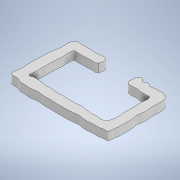
# Autodesk Inventor part: omega_patrat
Saved by Autodesk Inventor 2022.6 (Build 266554000, 554)
## iProperties
Created: 2024-11-29
Part Number: omega_patrat
Material: Generic
Document SubType Name: Modeling
Designer: Dragos Macovei
Density: 1 g/cm^3
Appearance: Default
Author: Dragos Macovei
Autodesk Inventor part; units mm, degrees
ref_plane "YZ Plane" through (0, 0, 0) normal (1, 0, 0) x (0, 1, 0)
ref_plane "XZ Plane" through (0, 0, 0) normal (0, 1, 0) x (-1, 0, 0)
ref_plane "XY Plane" through (0, 0, 0) normal (0, 0, 1) x (1, 0, 0)
sketch "Sketch1" plane through (0, 0, 0) normal (0, 1, 0) x (-1, 0, 0)
  line L0 (-66.777, 299.3906) -> (276.1714, 295.0556) construction
  line L1 (276.1714, 295.0556) -> (270.3914, -162.2089) construction
  line L2 (270.3914, -162.2089) -> (-72.557, -157.8739) construction
  line L3 (-72.557, -157.8739) -> (-66.777, 299.3906) construction
  line L4 (96.3483, 176.7256) -> (136.3483, 176.7256)
  line L5 (136.3483, 176.7256) -> (136.3483, 216.7256)
  line L6 (136.3483, 216.7256) -> (96.3483, 216.7256)
  line L7 (96.3483, 216.7256) -> (96.3483, 176.7256)
  spline S0 degree 5 poles (121.746, 189.6677) (121.8582, 189.8024) (122.1165, 190.0468) (122.696, 190.466) (123.267, 189.8642) (124.6453, 190.1774) (125.328, 190.0683) (126.8621, 190.3562) (128.3282, 190.0576) (129.112, 190.4967) (130.2239, 189.6634) (130.3851, 191.3616) (130.386, 192.2277) (130.4456, 193.2168) (130.098, 194.4317) (130.6414, 195.9554) (130.26, 197.268) (130.6866, 198.6376) (130.3499, 199.9474) (130.777, 201.8336) (130.3554, 202.4152) (130.6842, 203.8925) (130.4554, 204.6826) (130.7477, 205.6315) (130.835, 206.2315) (129.8137, 206.4041) (129.5759, 205.655) (128.3019, 205.9904) (127.631, 205.7744) (126.9754, 206.0105) (125.9738, 205.8252) (125.5897, 206.4444) (124.9227, 206.0743) (123.8224, 206.4023) (123.7203, 206.3457) (122.5113, 206.0601) (122.157, 206.5324) (121.0441, 206.2389) (120.3819, 206.6852) (119.6232, 206.4701) (117.036, 206.2938) (116.7323, 206.5852) (114.1771, 206.4506) (113.2716, 206.6097) (111.6878, 206.2504) (110.426, 206.1075) (109.1179, 206.8753) (108.3741, 206.3084) (107.0205, 207.3252) (105.4738, 206.2255) (104.5208, 207.1332) (101.2997, 206.9083) (101.9367, 204.5933) (101.1006, 204.794) (101.4951, 200.3084) (101.7262, 201.3801) (101.0749, 195.9532) (102.104, 194.9567) (100.8961, 191.7782) (102.0198, 190.7144) (102.3018, 191.2423) (103.3518, 191.0241) (104.1529, 191.0393) (104.914, 191.1531) (106.3556, 190.818) (106.9331, 190.6894) (107.5941, 190.7851) (108.6616, 191.0082) (109.5951, 190.8205) (110.226, 190.6347) (110.884, 189.6818) (110.3368, 188.8065) (110.3572, 188.1316) (110.5612, 187.3686) (109.7518, 186.984) (109.4345, 186.6326) (108.7664, 186.1921) (108.0478, 187.4743) (107.9195, 187.9274) (105.9688, 186.2366) (105.579, 187.9799) (104.6729, 187.6814) (103.1741, 187.3302) (102.2016, 187.7167) (100.7281, 186.8769) (100.1835, 188.1256) (99.0619, 187.4356) (98.5932, 188.7911) (98.2767, 189.0131) (98.2262, 190.1352) (98.1397, 191.5446) (98.2346, 192.1528) (98.3985, 194.3716) (98.073, 193.9662) (97.8455, 198.3926) (98.7798, 198.6808) (97.8366, 201.0867) (97.956, 202.903) (98.1221, 204.4291) (97.8543, 206.2027) (98.3732, 207.3771) (98.1322, 208.2019) (98.5683, 209.8021) (98.8147, 209.4139) (100.5555, 209.4661) (100.9972, 209.9948) (103.2743, 209.7444) (104.3228, 209.7586) (106.0751, 210.2206) (108.1074, 209.8047) (108.7444, 209.466) (110.6067, 209.9184) (111.2367, 209.9171) (113.9053, 210.0628) (114.3522, 209.9994) (116.608, 210.0205) (117.7825, 210.0415) (119.3895, 209.7172) (121.533, 210.2273) (123.3215, 209.4206) (124.9598, 209.8229) (126.838, 210.2204) (127.8277, 209.7644) (129.8941, 209.8151) (130.237, 209.8931) (131.5337, 208.8933) (131.8702, 209.3016) (132.5364, 208.9742) (133.6151, 209.2641) (134.5294, 208.8061) (134.7216, 207.7667) (133.6072, 204.6681) (134.7968, 202.1463) (133.8481, 198.4724) (134.5196, 195.9114) (133.1671, 191.4172) (133.6456, 189.992) (133.7121, 188.2772) (132.9584, 187.2211) (132.2502, 186.3053) (131.1337, 187.1404) (129.7612, 186.616) (128.3516, 187.0179) (126.5546, 186.7163) (125.4027, 187.4056) (124.0138, 186.438) (122.6452, 186.8345) (121.7613, 186.6506) (121.2217, 187.7352) (121.3717, 188.2192) (121.4927, 189.1283) (121.5396, 189.3738) (121.6519, 189.5549) (121.746, 189.6677) knots 0 0 0 0 0 0 0.006947 0.011757 0.018108 0.024839 0.031624 0.038107 0.044552 0.050761 0.056649 0.062728 0.069328 0.076188 0.083177 0.090521 0.09806 0.105274 0.1124 0.119309 0.125804 0.131543 0.136972 0.142021 0.147124 0.15223 0.157594 0.163183 0.168684 0.173938 0.179218 0.184251 0.189295 0.194439 0.19969 0.204827 0.210269 0.216373 0.222854 0.22993 0.237405 0.24524 0.252721 0.260133 0.266921 0.273611 0.280314 0.28715 0.294518 0.30215 0.309591 0.317516 0.325232 0.333499 0.342598 0.352417 0.361109 0.369188 0.375929 0.381633 0.386675 0.392306 0.398184 0.403979 0.409867 0.415742 0.42124 0.4269 0.43277 0.438443 0.443887 0.449275 0.454422 0.45926 0.464259 0.469213 0.474698 0.480482 0.486484 0.492733 0.499471 0.506046 0.512567 0.519103 0.525332 0.531082 0.536624 0.542428 0.548381 0.554624 0.561016 0.568398 0.575927 0.583911 0.592192 0.600997 0.60926 0.617256 0.624846 0.63185 0.637951 0.643731 0.649497 0.655604 0.662104 0.669587 0.677418 0.685186 0.692711 0.700043 0.707447 0.714542 0.722005 0.729536 0.737239 0.744995 0.753152 0.761357 0.769683 0.777992 0.786018 0.793434 0.800434 0.806634 0.812229 0.817499 0.822743 0.827813 0.833979 0.841528 0.850244 0.860305 0.871752 0.882896 0.89316 0.902362 0.910204 0.916781 0.923199 0.929777 0.93669 0.943955 0.951545 0.959116 0.966229 0.972799 0.978998 0.984809 0.990049 0.994177 1 1 1 1 1 1
  point P0 (0, 0)
  point P1 (123.2321, 190.1232)
  point P2 (124.3628, 190.0813)
  point P3 (125.368, 190.1441)
  point P4 (126.9176, 190.2279)
  point P5 (128.4043, 190.2279)
  point P6 (129.3048, 190.2069)
  point P7 (129.9748, 190.2069)
  point P8 (130.3308, 191.0864)
  point P9 (130.3936, 192.1963)
  point P10 (130.3727, 193.1176)
  point P11 (130.2889, 194.3322)
  point P12 (130.4355, 195.8608)
  point P13 (130.4355, 197.2638)
  point P14 (130.5193, 198.604)
  point P15 (130.5184, 200.1573)
  point P16 (130.5853, 201.7452)
  point P17 (130.5184, 202.6979)
  point P18 (130.5686, 203.9349)
  point P19 (130.5853, 204.9043)
  point P20 (130.719, 205.7234)
  point P21 (130.5853, 206.1245)
  point P22 (130.0671, 206.2248)
  point P23 (129.4821, 205.9407)
  point P24 (128.429, 205.8738)
  point P25 (127.5933, 205.8738)
  point P26 (126.8578, 205.924)
  point P27 (126.0388, 206.0243)
  point P28 (125.5373, 206.2248)
  point P29 (124.852, 206.2248)
  point P30 (123.9828, 206.3251)
  point P31 (123.5482, 206.3084)
  point P32 (122.7125, 206.2248)
  point P33 (122.0606, 206.3586)
  point P34 (121.2248, 206.392)
  point P35 (120.5228, 206.509)
  point P36 (119.7038, 206.5257)
  point P37 (117.6005, 206.3995)
  point P38 (116.3483, 206.4845)
  point P39 (114.4015, 206.5128)
  point P40 (113.0426, 206.4845)
  point P41 (111.6271, 206.2863)
  point P42 (110.2683, 206.3429)
  point P43 (109.1642, 206.5977)
  point P44 (108.3715, 206.626)
  point P45 (107.2108, 206.8525)
  point P46 (105.767, 206.6826)
  point P47 (104.1533, 206.8525)
  point P48 (102.0018, 206.258)
  point P49 (101.6337, 205.0973)
  point P50 (101.4356, 204.248)
  point P51 (101.4356, 201.7001)
  point P52 (101.5488, 200.4828)
  point P53 (101.4639, 196.7256)
  point P54 (101.5205, 193.5751)
  point P55 (101.6621, 191.282)
  point P56 (102.0584, 191.0273)
  point P57 (102.4264, 191.0839)
  point P58 (103.1625, 191.0839)
  point P59 (104.0401, 191.0556)
  point P60 (105.0026, 191.0556)
  point P61 (106.3332, 190.8291)
  point P62 (106.9843, 190.7442)
  point P63 (107.6071, 190.8008)
  point P64 (108.6263, 190.914)
  point P65 (109.5605, 190.8008)
  point P66 (110.2116, 190.4611)
  point P67 (110.608, 189.6677)
  point P68 (110.4381, 188.7625)
  point P69 (110.4025, 188.0334)
  point P70 (110.3144, 187.4235)
  point P71 (109.8302, 186.977)
  point P72 (109.3838, 186.6437)
  point P73 (108.8933, 186.5243)
  point P74 (108.2106, 187.2136)
  point P75 (107.7449, 187.5241)
  point P76 (106.2961, 187.0067)
  point P77 (105.4682, 187.5241)
  point P78 (104.6972, 187.6838)
  point P79 (103.3102, 187.4938)
  point P80 (102.0029, 187.4382)
  point P81 (100.7747, 187.3836)
  point P82 (99.9558, 187.7384)
  point P83 (99.1643, 187.9022)
  point P84 (98.6184, 188.5846)
  point P85 (98.3727, 189.1032)
  point P86 (98.2362, 189.9766)
  point P87 (98.1816, 191.314)
  point P88 (98.2362, 192.3512)
  point P89 (98.2908, 193.716)
  point P90 (98.1816, 194.4802)
  point P91 (98.1055, 197.5036)
  point P92 (98.3533, 199.1144)
  point P93 (98.0642, 201.0143)
  point P94 (97.9816, 202.9968)
  point P95 (98.0229, 204.6902)
  point P96 (98.0642, 206.3836)
  point P97 (98.2294, 207.4987)
  point P98 (98.312, 208.6139)
  point P99 (98.6011, 209.4399)
  point P100 (98.9172, 209.5225)
  point P101 (100.0054, 209.5225)
  point P102 (101.0792, 209.7703)
  point P103 (102.8552, 209.8116)
  point P104 (104.4247, 209.8529)
  point P105 (106.2833, 210.0182)
  point P106 (108.018, 209.7703)
  point P107 (109.0092, 209.6464)
  point P108 (110.2896, 209.8116)
  point P109 (111.4874, 209.9355)
  point P110 (113.5112, 210.0182)
  point P111 (114.6676, 210.0182)
  point P112 (116.3483, 210.0182)
  point P113 (117.7653, 209.9769)
  point P114 (119.2935, 209.8942)
  point P115 (121.4412, 209.9355)
  point P116 (123.3824, 209.6877)
  point P117 (125.1584, 209.8529)
  point P118 (126.8105, 210.0182)
  point P119 (128.2974, 209.8529)
  point P120 (129.8255, 209.8116)
  point P121 (130.6103, 209.5638)
  point P122 (131.5189, 209.1508)
  point P123 (131.9319, 209.1508)
  point P124 (132.4689, 209.1095)
  point P125 (133.4188, 209.1095)
  point P126 (134.1623, 208.8617)
  point P127 (134.4927, 208.2009)
  point P128 (134.2036, 205.8879)
  point P129 (134.2862, 202.4599)
  point P130 (134.2036, 198.784)
  point P131 (133.9971, 194.9016)
  point P132 (133.5014, 191.0192)
  point P133 (133.6045, 189.3768)
  point P134 (133.4206, 188.0895)
  point P135 (132.8459, 187.1241)
  point P136 (132.2138, 186.6989)
  point P137 (131.3059, 186.8138)
  point P138 (129.9727, 186.8253)
  point P139 (128.3614, 186.8646)
  point P140 (126.593, 186.9432)
  point P141 (125.2569, 187.0218)
  point P142 (123.8028, 186.7074)
  point P143 (122.506, 186.7467)
  point P144 (121.746, 187.0218)
  point P145 (121.3578, 187.7182)
  point P146 (121.3906, 188.4509)
  point P147 (121.5328, 189.2601)
  dimension "d1" = 40
  dimension "d2" = 40
  constraints: 8 end point, 2 parallel, 1 horizontal, 1 perpendicular, 151 other
  measures "d1" distance of L6.end L5.end
  measures "d2" distance of L5.end L4.end
extrude "Extrusion1" add sketch "Sketch1" along normal blind 3 contours S0
body "Solid1"
